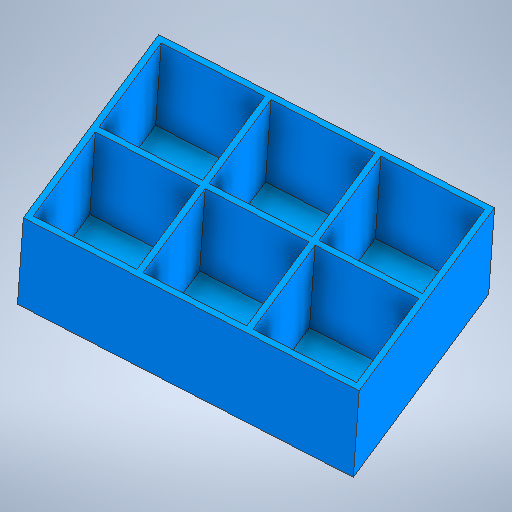
# Autodesk Inventor part: Kistenfach
Saved by Autodesk Inventor 2026.1 (Build 301233020, 233B)
## iProperties
Created: 2026-03-23
Part Number: Kistenfach
Material: Generisch
Document SubType Name: Modeling
Designer: Pc
Density: 1 g/cm^3
Appearance: Vorgabe
Author: Pc
Autodesk Inventor part; units mm, degrees
ref_plane "YZ Plane" through (0, 0, 0) normal (1, 0, 0) x (0, 1, 0)
ref_plane "XZ Plane" through (0, 0, 0) normal (0, 1, 0) x (-1, 0, 0)
ref_plane "XY Plane" through (0, 0, 0) normal (0, 0, 1) x (1, 0, 0)
sketch "Skizze1" plane through (0, 0, 0) normal (0, 0, 1) x (1, 0, 0)
  line L0 (-81, -31.5) -> (81, -31.5)
  line L1 (81, -31.5) -> (81, 31.5)
  line L2 (81, 31.5) -> (-81, 31.5)
  line L3 (-81, 31.5) -> (-81, -31.5)
  line L4 (-81, -31.5) -> (81, 31.5) construction
  line L5 (81, -31.5) -> (-81, 31.5) construction
  point P0 (0, 0)
  dimension "d0" = 162
  dimension "d1" = 63
  constraints: 12 end point, 2 midpoint, 2 parallel, 1 horizontal, 1 perpendicular
  measures "d0" distance of L2.end L1.end
  measures "d1" distance of L1.end L0.end
extrude "Extrusion1" add sketch "Skizze1" along normal blind 109
sketch "Skizze2" plane through (-81, 31.5, 0) normal (0, 1, 0) x (1, 0, 0)
  line L0 (3, -3) -> (53, -3)
  line L1 (53, -3) -> (53, -53)
  line L2 (53, -53) -> (3, -53)
  line L3 (3, -53) -> (3, -3)
  line L4 (3, -56) -> (53, -56)
  line L5 (53, -56) -> (53, -106)
  line L6 (53, -106) -> (3, -106)
  line L7 (3, -106) -> (3, -56)
  point P0 (81, 0)
  dimension "d4" = 50
  dimension "d5" = 50
  dimension "d6" = 50
  dimension "d7" = 50
  constraints: 16 end point, 4 parallel, 2 horizontal, 2 perpendicular
  measures "d4" distance of L1.end L2.end
  measures "d5" distance of L0.end L1.end
  measures "d6" distance of L5.end L6.end
  measures "d7" distance of L4.end L5.end
extrude "Extrusion2" cut sketch "Skizze2" against normal blind 60 contours L0 L1 L2 L3
sketch "Skizze3" plane through (-81, 31.5, 0) normal (0, 1, 0) x (1, 0, 0)
  line L0 (3, -56) -> (53, -56)
  line L1 (53, -56) -> (53, -106)
  line L2 (53, -106) -> (3, -106)
  line L3 (3, -106) -> (3, -56)
  point P0 (81, 0)
  dimension "d10" = 50
  dimension "d11" = 50
  constraints: 8 end point, 2 parallel, 1 horizontal, 1 perpendicular
  measures "d10" distance of L1.end L2.end
  measures "d11" distance of L0.end L1.end
extrude "Extrusion3" cut sketch "Skizze3" against normal blind 60
sketch "Skizze4" plane through (-81, 31.5, 0) normal (0, 1, 0) x (1, 0, 0)
  line L0 (56, -3) -> (106, -3)
  line L1 (106, -3) -> (106, -53)
  line L2 (106, -53) -> (56, -53)
  line L3 (56, -53) -> (56, -3)
  point P0 (81, 0)
  dimension "d14" = 50
  dimension "d15" = 50
  constraints: 8 end point, 2 parallel, 1 horizontal, 1 perpendicular
  measures "d14" distance of L1.end L2.end
  measures "d15" distance of L0.end L1.end
extrude "Extrusion4" cut sketch "Skizze4" against normal blind 60
sketch "Skizze5" plane through (-81, 31.5, 0) normal (0, 1, 0) x (1, 0, 0)
  line L0 (56, -56) -> (106, -56)
  line L1 (106, -56) -> (106, -106)
  line L2 (106, -106) -> (56, -106)
  line L3 (56, -106) -> (56, -56)
  point P0 (81, 0)
  dimension "d18" = 50
  dimension "d19" = 50
  constraints: 8 end point, 2 parallel, 1 horizontal, 1 perpendicular
  measures "d18" distance of L1.end L2.end
  measures "d19" distance of L0.end L1.end
extrude "Extrusion5" cut sketch "Skizze5" against normal blind 60
sketch "Skizze6" plane through (-81, 31.5, 0) normal (0, 1, 0) x (1, 0, 0)
  line L0 (109, -3) -> (159, -3)
  line L1 (159, -3) -> (159, -53)
  line L2 (159, -53) -> (109, -53)
  line L3 (109, -53) -> (109, -3)
  point P0 (81, 0)
  dimension "d22" = 50
  dimension "d23" = 50
  constraints: 8 end point, 2 parallel, 1 horizontal, 1 perpendicular
  measures "d22" distance of L1.end L2.end
  measures "d23" distance of L0.end L1.end
extrude "Extrusion6" cut sketch "Skizze6" against normal blind 60
sketch "Skizze7" plane through (-81, 31.5, 0) normal (0, 1, 0) x (1, 0, 0)
  line L0 (109, -56) -> (159, -56)
  line L1 (159, -56) -> (159, -106)
  line L2 (159, -106) -> (109, -106)
  line L3 (109, -106) -> (109, -56)
  point P0 (81, 0)
  dimension "d26" = 50
  dimension "d27" = 50
  constraints: 8 end point, 2 parallel, 1 horizontal, 1 perpendicular
  measures "d26" distance of L1.end L2.end
  measures "d27" distance of L0.end L1.end
extrude "Extrusion7" cut sketch "Skizze7" against normal blind 60
